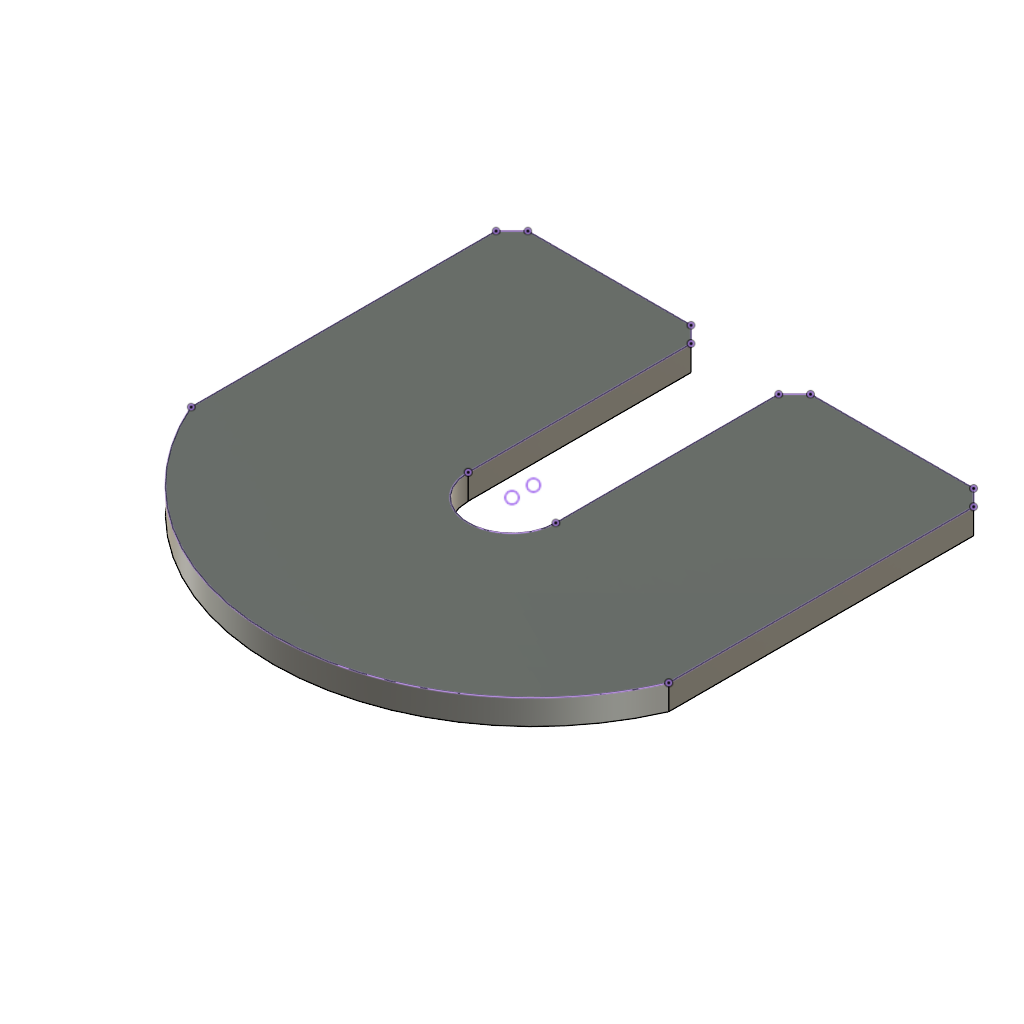
Locking Plate Spacer (Autodesk Fusion 360 design; units mm, degrees)
Autodesk Fusion 360 part; units mm, degrees
sketch "Overall Plate" plane through (0, 0, 0) normal (0, 0, 1) x (1, 0, 0)
  line L0 (19.05, 19.05) -> (-19.05, 19.05)
  line L1 (-19.05, 19.05) -> (-19.05, -19.05)
  line L2 (-19.05, -19.05) -> (19.05, -19.05)
  line L3 (19.05, -19.05) -> (19.05, 19.05)
  line L4 (19.05, 19.05) -> (-19.05, -19.05) construction
  line L5 (-19.05, 19.05) -> (19.05, -19.05) construction
  circle A0 centre (0, 0) radius 3.4925
  line L6 (-3.4925, 19.05) -> (-3.4925, 0)
  line L7 (3.4925, 19.05) -> (3.4925, 0)
  dimension "d1" = 38.1
  dimension "d2" = 38.1
  dimension "d3" = 6.985
  dimension "d5" = 19.05
  constraint horizontal L0
  constraint perpendicular L0 L1
  constraint parallel L0 L2
  constraint parallel L1 L3
  constraint coincident L4 A0.centre
  constraint coincident L5 A0.centre
  constraint coincident A0.centre origin
  constraint coincident L0 L6.start
  constraint coincident A0 L6.end
  constraint tangent A0 L6
  constraint vertical L6
  constraint coincident L0 L7.start
  constraint coincident A0 L7.end
  constraint tangent A0 L7
  constraint vertical L7
  measures "d1" distance of L1 L3
  measures "d2" distance of L0 L2
  measures "d3" diameter of A0
  measures "d5" distance of L0 A0.centre
extrude "Extrude1" add sketch "Overall Plate" along normal blind 2 contours L0 L1 L2 L3 A0 L6 L7
sketch "Rounded Nose" plane through (0, 0, 2) normal (0, 0, 1) x (-1, 0, 0)
  arc A0 (19.05, 6.5433) -> (-19.05, 6.5433) centre (0, -1.7117) ccw
  line L0 (19.05, -19.05) -> (19.05, 19.05)
  line L1 (3.4925, -19.05) -> (19.05, -19.05)
  line L2 (19.05, -19.05) -> (19.05, 19.05)
  line L3 (19.05, 19.05) -> (-19.05, 19.05)
  line L4 (-19.05, 19.05) -> (-19.05, -19.05)
  line L5 (-19.05, -19.05) -> (-3.4925, -19.05)
  line L6 (-3.4925, -19.05) -> (-3.4925, 0)
  arc A1 (-3.4925, 0) -> (3.4925, 0) centre (0, 0) cw
  line L7 (3.4925, 0) -> (3.4925, -19.05)
  line L8 (19.05, 6.5433) -> (-19.05, 6.5433) construction
  dimension "d8" = 8.255
  constraint coincident A0.start L0
  constraint coincident A0.end L4
  constraint tangent A0 L3
  constraint horizontal L8
  measures "d8" distance of A0.centre L8
extrude "Extrude2" cut sketch "Rounded Nose" against normal blind 2.0066 contours A0 L0 L2 L3 | A0 L3 L4
chamfer "Chamfer1" distance 1.27 angle 45 4 edges at (-19.05, 19.05, 1) (-3.4925, 19.05, 1) (3.4925, 19.05, 1) (19.05, 19.05, 1) tangent chain off
sketch "For DXF Export" plane through (0, 0, 2) normal (0, 0, 1) x (-1, 0, 0)
  line L0 (-19.05, -17.78) -> (-17.78, -19.05)
  line L1 (-17.78, -19.05) -> (-4.7625, -19.05)
  line L2 (-4.7625, -19.05) -> (-3.4925, -17.78)
  line L3 (-3.4925, -17.78) -> (-3.4925, 0)
  arc A0 (-3.4925, 0) -> (3.4925, 0) centre (0, 0) cw
  line L4 (3.4925, 0) -> (3.4925, -17.78)
  line L5 (3.4925, -17.78) -> (4.7625, -19.05)
  line L6 (4.7625, -19.05) -> (17.78, -19.05)
  line L7 (17.78, -19.05) -> (19.05, -17.78)
  line L8 (19.05, -17.78) -> (19.05, 6.5433)
  arc A1 (19.05, 6.5433) -> (-19.05, 6.5433) centre (0, -1.7117) ccw
  line L9 (-19.05, 6.5433) -> (-19.05, -17.78)
